Autodesk Fusion 360 part; units mm, degrees
(part 5 of 7)
extrude "Washer clearance (2)''" cut sketch "Washer clearance (1) (3)" along normal blind 0.4 bodies 36 in component "HARDWARE | M3x10 countersunk hip · reference"
ref_plane "WorkPlane11" through (0, 0, 1.2) normal (0, 0, 1) x (1, 0, 0) in component "HARDWARE | M3x10 countersunk hip · reference"
sketch "M3 underside nut (1)" plane through (0, 0, 1.2) normal (0, 0, 1) x (1, 0, 0) in component "HARDWARE | M3x10 countersunk hip · reference"
  line L0 (45.1754, 4) -> (43.5877, 6.75)
  line L1 (43.5877, 6.75) -> (40.4123, 6.75)
  line L2 (40.4123, 6.75) -> (38.8246, 4)
  line L3 (38.8246, 4) -> (40.4123, 1.25)
  line L4 (40.4123, 1.25) -> (43.5877, 1.25)
  line L5 (43.5877, 1.25) -> (45.1754, 4)
extrude "M3 underside nut (2)" add sketch "M3 underside nut (1)" along normal blind 2.4 separate body makes body 37 in component "HARDWARE | M3x10 countersunk hip · reference"
ref_plane "WorkPlane12" through (0, 0, 1.2) normal (0, 0, 1) x (1, 0, 0) in component "HARDWARE | M3x10 countersunk hip · reference"
sketch "Nut thread envelope clearance (1) (3)" plane through (0, 0, 1.2) normal (0, 0, 1) x (1, 0, 0) in component "HARDWARE | M3x10 countersunk hip · reference"
  circle A0 centre (42, 4) radius 1.65
extrude "Nut thread envelope clearance (2)''" cut sketch "Nut thread envelope clearance (1) (3)" along normal blind 2.4 bodies 37 in component "HARDWARE | M3x10 countersunk hip · reference"
ref_plane "WorkPlane1" through (0, 4, 0) normal (0, 1, 0) x (0, 0, 1) in component "HARDWARE | M2x30 knee towers · unthreaded reference"
sketch "Bolt shank (3)" plane through (0, 4, 0) normal (0, 1, 0) x (1, 0, 0) in component "HARDWARE | M2x30 knee towers · unthreaded reference"
  circle A0 centre (22.5, 10) radius 1
extrude "Bolt shank (1)''" add sketch "Bolt shank (3)" along normal blind 30 separate body makes body 38 in component "HARDWARE | M2x30 knee towers · unthreaded reference"
ref_plane "WorkPlane2" through (0, 2, 0) normal (0, 1, 0) x (0, 0, 1) in component "HARDWARE | M2x30 knee towers · unthreaded reference"
sketch "Socket head envelope (3)" plane through (0, 2, 0) normal (0, 1, 0) x (1, 0, 0) in component "HARDWARE | M2x30 knee towers · unthreaded reference"
  circle A0 centre (22.5, 10) radius 1.9
extrude "Socket head envelope (1)''" add sketch "Socket head envelope (3)" along normal blind 2 bodies 38 in component "HARDWARE | M2x30 knee towers · unthreaded reference"
ref_plane "WorkPlane3" through (0, 28, 0) normal (0, 1, 0) x (0, 0, 1) in component "HARDWARE | M2x30 knee towers · unthreaded reference"
sketch "Washer (3)" plane through (0, 28, 0) normal (0, 1, 0) x (1, 0, 0) in component "HARDWARE | M2x30 knee towers · unthreaded reference"
  circle A0 centre (22.5, 10) radius 2
extrude "Washer (1)''" add sketch "Washer (3)" along normal blind 0.4 separate body makes body 39 in component "HARDWARE | M2x30 knee towers · unthreaded reference"
ref_plane "WorkPlane4" through (0, 28, 0) normal (0, 1, 0) x (0, 0, 1) in component "HARDWARE | M2x30 knee towers · unthreaded reference"
sketch "Washer clearance (4)" plane through (0, 28, 0) normal (0, 1, 0) x (1, 0, 0) in component "HARDWARE | M2x30 knee towers · unthreaded reference"
  circle A0 centre (22.5, 10) radius 1.2
extrude "Washer clearance (1)'''" cut sketch "Washer clearance (4)" along normal blind 0.4 bodies 39 in component "HARDWARE | M2x30 knee towers · unthreaded reference"
ref_plane "WorkPlane5" through (0, 28.4, 0) normal (0, 1, 0) x (0, 0, 1) in component "HARDWARE | M2x30 knee towers · unthreaded reference"
sketch "Hex nut (3)" plane through (0, 28.4, 0) normal (0, 1, 0) x (1, 0, 0) in component "HARDWARE | M2x30 knee towers · unthreaded reference"
  line L0 (24.8094, 10) -> (23.6547, 8)
  line L1 (23.6547, 8) -> (21.3453, 8)
  line L2 (21.3453, 8) -> (20.1906, 10)
  line L3 (20.1906, 10) -> (21.3453, 12)
  line L4 (21.3453, 12) -> (23.6547, 12)
  line L5 (23.6547, 12) -> (24.8094, 10)
extrude "Hex nut (1)''" add sketch "Hex nut (3)" along normal blind 1.6 separate body makes body 40 in component "HARDWARE | M2x30 knee towers · unthreaded reference"
ref_plane "WorkPlane6" through (0, 28.4, 0) normal (0, 1, 0) x (0, 0, 1) in component "HARDWARE | M2x30 knee towers · unthreaded reference"
sketch "Nut thread envelope clearance (4)" plane through (0, 28.4, 0) normal (0, 1, 0) x (1, 0, 0) in component "HARDWARE | M2x30 knee towers · unthreaded reference"
  circle A0 centre (22.5, 10) radius 1.15
extrude "Nut thread envelope clearance (1)'''" cut sketch "Nut thread envelope clearance (4)" along normal blind 1.6 bodies 40 in component "HARDWARE | M2x30 knee towers · unthreaded reference"
ref_plane "WorkPlane7" through (0, 4, 0) normal (0, 1, 0) x (0, 0, 1) in component "HARDWARE | M2x30 knee towers · unthreaded reference"
sketch "Bolt shank (1) (3)" plane through (0, 4, 0) normal (0, 1, 0) x (1, 0, 0) in component "HARDWARE | M2x30 knee towers · unthreaded reference"
  circle A0 centre (22.5, -10) radius 1
extrude "Bolt shank (2)''" add sketch "Bolt shank (1) (3)" along normal blind 30 separate body makes body 41 in component "HARDWARE | M2x30 knee towers · unthreaded reference"
ref_plane "WorkPlane8" through (0, 2, 0) normal (0, 1, 0) x (0, 0, 1) in component "HARDWARE | M2x30 knee towers · unthreaded reference"
sketch "Socket head envelope (1) (3)" plane through (0, 2, 0) normal (0, 1, 0) x (1, 0, 0) in component "HARDWARE | M2x30 knee towers · unthreaded reference"
  circle A0 centre (22.5, -10) radius 1.9
extrude "Socket head envelope (2)''" add sketch "Socket head envelope (1) (3)" along normal blind 2 bodies 41 in component "HARDWARE | M2x30 knee towers · unthreaded reference"
ref_plane "WorkPlane9" through (0, 28, 0) normal (0, 1, 0) x (0, 0, 1) in component "HARDWARE | M2x30 knee towers · unthreaded reference"
sketch "Washer (1) (3)" plane through (0, 28, 0) normal (0, 1, 0) x (1, 0, 0) in component "HARDWARE | M2x30 knee towers · unthreaded reference"
  circle A0 centre (22.5, -10) radius 2
extrude "Washer (2)''" add sketch "Washer (1) (3)" along normal blind 0.4 separate body makes body 42 in component "HARDWARE | M2x30 knee towers · unthreaded reference"
ref_plane "WorkPlane10" through (0, 28, 0) normal (0, 1, 0) x (0, 0, 1) in component "HARDWARE | M2x30 knee towers · unthreaded reference"
sketch "Washer clearance (1) (4)" plane through (0, 28, 0) normal (0, 1, 0) x (1, 0, 0) in component "HARDWARE | M2x30 knee towers · unthreaded reference"
  circle A0 centre (22.5, -10) radius 1.2
extrude "Washer clearance (2)'''" cut sketch "Washer clearance (1) (4)" along normal blind 0.4 bodies 42 in component "HARDWARE | M2x30 knee towers · unthreaded reference"
ref_plane "WorkPlane11" through (0, 28.4, 0) normal (0, 1, 0) x (0, 0, 1) in component "HARDWARE | M2x30 knee towers · unthreaded reference"
sketch "Hex nut (1) (3)" plane through (0, 28.4, 0) normal (0, 1, 0) x (1, 0, 0) in component "HARDWARE | M2x30 knee towers · unthreaded reference"
  line L0 (24.8094, -10) -> (23.6547, -12)
  line L1 (23.6547, -12) -> (21.3453, -12)
  line L2 (21.3453, -12) -> (20.1906, -10)
  line L3 (20.1906, -10) -> (21.3453, -8)
  line L4 (21.3453, -8) -> (23.6547, -8)
  line L5 (23.6547, -8) -> (24.8094, -10)
extrude "Hex nut (2)''" add sketch "Hex nut (1) (3)" along normal blind 1.6 separate body makes body 43 in component "HARDWARE | M2x30 knee towers · unthreaded reference"
ref_plane "WorkPlane12" through (0, 28.4, 0) normal (0, 1, 0) x (0, 0, 1) in component "HARDWARE | M2x30 knee towers · unthreaded reference"
sketch "Nut thread envelope clearance (1) (4)" plane through (0, 28.4, 0) normal (0, 1, 0) x (1, 0, 0) in component "HARDWARE | M2x30 knee towers · unthreaded reference"
  circle A0 centre (22.5, -10) radius 1.15
extrude "Nut thread envelope clearance (2)'''" cut sketch "Nut thread envelope clearance (1) (4)" along normal blind 1.6 bodies 43 in component "HARDWARE | M2x30 knee towers · unthreaded reference"
sketch "Bolt shank (4)" plane through (0, 0, 0) normal (0, 0, 1) x (1, 0, 0) in component "HARDWARE | M3x50 chassis stack · unthreaded reference"
  circle A0 centre (27.7128, -16) radius 1.5
extrude "Bolt shank (1)'''" add sketch "Bolt shank (4)" along normal blind 50 separate body makes body 44 in component "HARDWARE | M3x50 chassis stack · unthreaded reference"
ref_plane "WorkPlane1" through (0, 0, -3) normal (0, 0, 1) x (1, 0, 0) in component "HARDWARE | M3x50 chassis stack · unthreaded reference"
sketch "Socket head envelope (4)" plane through (0, 0, -3) normal (0, 0, 1) x (1, 0, 0) in component "HARDWARE | M3x50 chassis stack · unthreaded reference"
  circle A0 centre (27.7128, -16) radius 2.8
extrude "Socket head envelope (1)'''" add sketch "Socket head envelope (4)" along normal blind 3 bodies 44 in component "HARDWARE | M3x50 chassis stack · unthreaded reference"
ref_plane "WorkPlane2" through (0, 0, 44) normal (0, 0, 1) x (1, 0, 0) in component "HARDWARE | M3x50 chassis stack · unthreaded reference"
sketch "Washer (4)" plane through (0, 0, 44) normal (0, 0, 1) x (1, 0, 0) in component "HARDWARE | M3x50 chassis stack · unthreaded reference"
  circle A0 centre (27.7128, -16) radius 2.75
extrude "Washer (1)'''" add sketch "Washer (4)" along normal blind 0.4 separate body makes body 45 in component "HARDWARE | M3x50 chassis stack · unthreaded reference"
ref_plane "WorkPlane3" through (0, 0, 44) normal (0, 0, 1) x (1, 0, 0) in component "HARDWARE | M3x50 chassis stack · unthreaded reference"
sketch "Washer clearance (5)" plane through (0, 0, 44) normal (0, 0, 1) x (1, 0, 0) in component "HARDWARE | M3x50 chassis stack · unthreaded reference"
  circle A0 centre (27.7128, -16) radius 1.7
extrude "Washer clearance (1)''''" cut sketch "Washer clearance (5)" along normal blind 0.4 bodies 45 in component "HARDWARE | M3x50 chassis stack · unthreaded reference"
ref_plane "WorkPlane4" through (0, 0, 44.4) normal (0, 0, 1) x (1, 0, 0) in component "HARDWARE | M3x50 chassis stack · unthreaded reference"
sketch "Hex nut (4)" plane through (0, 0, 44.4) normal (0, 0, 1) x (1, 0, 0) in component "HARDWARE | M3x50 chassis stack · unthreaded reference"
  line L0 (30.8882, -16) -> (29.3005, -13.25)
  line L1 (29.3005, -13.25) -> (26.1251, -13.25)
  line L2 (26.1251, -13.25) -> (24.5374, -16)
  line L3 (24.5374, -16) -> (26.1251, -18.75)
  line L4 (26.1251, -18.75) -> (29.3005, -18.75)
  line L5 (29.3005, -18.75) -> (30.8882, -16)
extrude "Hex nut (1)'''" add sketch "Hex nut (4)" along normal blind 2.4 separate body makes body 46 in component "HARDWARE | M3x50 chassis stack · unthreaded reference"
ref_plane "WorkPlane5" through (0, 0, 44.4) normal (0, 0, 1) x (1, 0, 0) in component "HARDWARE | M3x50 chassis stack · unthreaded reference"
sketch "Nut thread envelope clearance (5)" plane through (0, 0, 44.4) normal (0, 0, 1) x (1, 0, 0) in component "HARDWARE | M3x50 chassis stack · unthreaded reference"
  circle A0 centre (27.7128, -16) radius 1.65
extrude "Nut thread envelope clearance (1)''''" cut sketch "Nut thread envelope clearance (5)" along normal blind 2.4 bodies 46 in component "HARDWARE | M3x50 chassis stack · unthreaded reference"
sketch "Bolt shank (1) (4)" plane through (0, 0, 0) normal (0, 0, 1) x (1, 0, 0) in component "HARDWARE | M3x50 chassis stack · unthreaded reference"
  circle A0 centre (0, -32) radius 1.5
extrude "Bolt shank (2)'''" add sketch "Bolt shank (1) (4)" along normal blind 50 separate body makes body 47 in component "HARDWARE | M3x50 chassis stack · unthreaded reference"
ref_plane "WorkPlane6" through (0, 0, -3) normal (0, 0, 1) x (1, 0, 0) in component "HARDWARE | M3x50 chassis stack · unthreaded reference"
sketch "Socket head envelope (1) (4)" plane through (0, 0, -3) normal (0, 0, 1) x (1, 0, 0) in component "HARDWARE | M3x50 chassis stack · unthreaded reference"
  circle A0 centre (0, -32) radius 2.8
extrude "Socket head envelope (2)'''" add sketch "Socket head envelope (1) (4)" along normal blind 3 bodies 47 in component "HARDWARE | M3x50 chassis stack · unthreaded reference"
ref_plane "WorkPlane7" through (0, 0, 44) normal (0, 0, 1) x (1, 0, 0) in component "HARDWARE | M3x50 chassis stack · unthreaded reference"
sketch "Washer (1) (4)" plane through (0, 0, 44) normal (0, 0, 1) x (1, 0, 0) in component "HARDWARE | M3x50 chassis stack · unthreaded reference"
  circle A0 centre (0, -32) radius 2.75
extrude "Washer (2)'''" add sketch "Washer (1) (4)" along normal blind 0.4 separate body makes body 48 in component "HARDWARE | M3x50 chassis stack · unthreaded reference"
ref_plane "WorkPlane8" through (0, 0, 44) normal (0, 0, 1) x (1, 0, 0) in component "HARDWARE | M3x50 chassis stack · unthreaded reference"
sketch "Washer clearance (1) (5)" plane through (0, 0, 44) normal (0, 0, 1) x (1, 0, 0) in component "HARDWARE | M3x50 chassis stack · unthreaded reference"
  circle A0 centre (0, -32) radius 1.7
extrude "Washer clearance (2)''''" cut sketch "Washer clearance (1) (5)" along normal blind 0.4 bodies 48 in component "HARDWARE | M3x50 chassis stack · unthreaded reference"
ref_plane "WorkPlane9" through (0, 0, 44.4) normal (0, 0, 1) x (1, 0, 0) in component "HARDWARE | M3x50 chassis stack · unthreaded reference"
sketch "Hex nut (1) (4)" plane through (0, 0, 44.4) normal (0, 0, 1) x (1, 0, 0) in component "HARDWARE | M3x50 chassis stack · unthreaded reference"
  line L0 (3.1754, -32) -> (1.5877, -29.25)
  line L1 (1.5877, -29.25) -> (-1.5877, -29.25)
  line L2 (-1.5877, -29.25) -> (-3.1754, -32)
  line L3 (-3.1754, -32) -> (-1.5877, -34.75)
  line L4 (-1.5877, -34.75) -> (1.5877, -34.75)
  line L5 (1.5877, -34.75) -> (3.1754, -32)
extrude "Hex nut (2)'''" add sketch "Hex nut (1) (4)" along normal blind 2.4 separate body makes body 49 in component "HARDWARE | M3x50 chassis stack · unthreaded reference"
ref_plane "WorkPlane10" through (0, 0, 44.4) normal (0, 0, 1) x (1, 0, 0) in component "HARDWARE | M3x50 chassis stack · unthreaded reference"
sketch "Nut thread envelope clearance (1) (5)" plane through (0, 0, 44.4) normal (0, 0, 1) x (1, 0, 0) in component "HARDWARE | M3x50 chassis stack · unthreaded reference"
  circle A0 centre (0, -32) radius 1.65
extrude "Nut thread envelope clearance (2)''''" cut sketch "Nut thread envelope clearance (1) (5)" along normal blind 2.4 bodies 49 in component "HARDWARE | M3x50 chassis stack · unthreaded reference"
sketch "Bolt shank (2) (2)" plane through (0, 0, 0) normal (0, 0, 1) x (1, 0, 0) in component "HARDWARE | M3x50 chassis stack · unthreaded reference"
  circle A0 centre (-27.7128, -16) radius 1.5
extrude "Bolt shank (3)" add sketch "Bolt shank (2) (2)" along normal blind 50 separate body makes body 50 in component "HARDWARE | M3x50 chassis stack · unthreaded reference"
ref_plane "WorkPlane11" through (0, 0, -3) normal (0, 0, 1) x (1, 0, 0) in component "HARDWARE | M3x50 chassis stack · unthreaded reference"
sketch "Socket head envelope (2) (2)" plane through (0, 0, -3) normal (0, 0, 1) x (1, 0, 0) in component "HARDWARE | M3x50 chassis stack · unthreaded reference"
  circle A0 centre (-27.7128, -16) radius 2.8
extrude "Socket head envelope (3)" add sketch "Socket head envelope (2) (2)" along normal blind 3 bodies 50 in component "HARDWARE | M3x50 chassis stack · unthreaded reference"
ref_plane "WorkPlane12" through (0, 0, 44) normal (0, 0, 1) x (1, 0, 0) in component "HARDWARE | M3x50 chassis stack · unthreaded reference"
sketch "Washer (2) (2)" plane through (0, 0, 44) normal (0, 0, 1) x (1, 0, 0) in component "HARDWARE | M3x50 chassis stack · unthreaded reference"
  circle A0 centre (-27.7128, -16) radius 2.75
extrude "Washer (3)" add sketch "Washer (2) (2)" along normal blind 0.4 separate body makes body 51 in component "HARDWARE | M3x50 chassis stack · unthreaded reference"
ref_plane "WorkPlane13" through (0, 0, 44) normal (0, 0, 1) x (1, 0, 0) in component "HARDWARE | M3x50 chassis stack · unthreaded reference"
sketch "Washer clearance (2) (2)" plane through (0, 0, 44) normal (0, 0, 1) x (1, 0, 0) in component "HARDWARE | M3x50 chassis stack · unthreaded reference"
  circle A0 centre (-27.7128, -16) radius 1.7
extrude "Washer clearance (3)" cut sketch "Washer clearance (2) (2)" along normal blind 0.4 bodies 51 in component "HARDWARE | M3x50 chassis stack · unthreaded reference"
ref_plane "WorkPlane14" through (0, 0, 44.4) normal (0, 0, 1) x (1, 0, 0) in component "HARDWARE | M3x50 chassis stack · unthreaded reference"
sketch "Hex nut (2) (2)" plane through (0, 0, 44.4) normal (0, 0, 1) x (1, 0, 0) in component "HARDWARE | M3x50 chassis stack · unthreaded reference"
  line L0 (-24.5374, -16) -> (-26.1251, -13.25)
  line L1 (-26.1251, -13.25) -> (-29.3005, -13.25)
  line L2 (-29.3005, -13.25) -> (-30.8882, -16)
  line L3 (-30.8882, -16) -> (-29.3005, -18.75)
  line L4 (-29.3005, -18.75) -> (-26.1251, -18.75)
  line L5 (-26.1251, -18.75) -> (-24.5374, -16)
extrude "Hex nut (3)" add sketch "Hex nut (2) (2)" along normal blind 2.4 separate body makes body 52 in component "HARDWARE | M3x50 chassis stack · unthreaded reference"
ref_plane "WorkPlane15" through (0, 0, 44.4) normal (0, 0, 1) x (1, 0, 0) in component "HARDWARE | M3x50 chassis stack · unthreaded reference"
sketch "Nut thread envelope clearance (2) (2)" plane through (0, 0, 44.4) normal (0, 0, 1) x (1, 0, 0) in component "HARDWARE | M3x50 chassis stack · unthreaded reference"
  circle A0 centre (-27.7128, -16) radius 1.65
extrude "Nut thread envelope clearance (3)" cut sketch "Nut thread envelope clearance (2) (2)" along normal blind 2.4 bodies 52 in component "HARDWARE | M3x50 chassis stack · unthreaded reference"
sketch "Bolt shank (3) (2)" plane through (0, 0, 0) normal (0, 0, 1) x (1, 0, 0) in component "HARDWARE | M3x50 chassis stack · unthreaded reference"
  circle A0 centre (-27.7128, 16) radius 1.5
extrude "Bolt shank (4)" add sketch "Bolt shank (3) (2)" along normal blind 50 separate body makes body 53 in component "HARDWARE | M3x50 chassis stack · unthreaded reference"
ref_plane "WorkPlane16" through (0, 0, -3) normal (0, 0, 1) x (1, 0, 0) in component "HARDWARE | M3x50 chassis stack · unthreaded reference"
sketch "Socket head envelope (3) (2)" plane through (0, 0, -3) normal (0, 0, 1) x (1, 0, 0) in component "HARDWARE | M3x50 chassis stack · unthreaded reference"
  circle A0 centre (-27.7128, 16) radius 2.8
extrude "Socket head envelope (4)" add sketch "Socket head envelope (3) (2)" along normal blind 3 bodies 53 in component "HARDWARE | M3x50 chassis stack · unthreaded reference"
ref_plane "WorkPlane17" through (0, 0, 44) normal (0, 0, 1) x (1, 0, 0) in component "HARDWARE | M3x50 chassis stack · unthreaded reference"
sketch "Washer (3) (2)" plane through (0, 0, 44) normal (0, 0, 1) x (1, 0, 0) in component "HARDWARE | M3x50 chassis stack · unthreaded reference"
  circle A0 centre (-27.7128, 16) radius 2.75
extrude "Washer (4)" add sketch "Washer (3) (2)" along normal blind 0.4 separate body makes body 54 in component "HARDWARE | M3x50 chassis stack · unthreaded reference"
ref_plane "WorkPlane18" through (0, 0, 44) normal (0, 0, 1) x (1, 0, 0) in component "HARDWARE | M3x50 chassis stack · unthreaded reference"
sketch "Washer clearance (3) (2)" plane through (0, 0, 44) normal (0, 0, 1) x (1, 0, 0) in component "HARDWARE | M3x50 chassis stack · unthreaded reference"
  circle A0 centre (-27.7128, 16) radius 1.7
extrude "Washer clearance (4)" cut sketch "Washer clearance (3) (2)" along normal blind 0.4 bodies 54 in component "HARDWARE | M3x50 chassis stack · unthreaded reference"
ref_plane "WorkPlane19" through (0, 0, 44.4) normal (0, 0, 1) x (1, 0, 0) in component "HARDWARE | M3x50 chassis stack · unthreaded reference"
sketch "Hex nut (3) (2)" plane through (0, 0, 44.4) normal (0, 0, 1) x (1, 0, 0) in component "HARDWARE | M3x50 chassis stack · unthreaded reference"
  line L0 (-24.5374, 16) -> (-26.1251, 18.75)
  line L1 (-26.1251, 18.75) -> (-29.3005, 18.75)
  line L2 (-29.3005, 18.75) -> (-30.8882, 16)
  line L3 (-30.8882, 16) -> (-29.3005, 13.25)
  line L4 (-29.3005, 13.25) -> (-26.1251, 13.25)
  line L5 (-26.1251, 13.25) -> (-24.5374, 16)
extrude "Hex nut (4)" add sketch "Hex nut (3) (2)" along normal blind 2.4 separate body makes body 55 in component "HARDWARE | M3x50 chassis stack · unthreaded reference"
ref_plane "WorkPlane20" through (0, 0, 44.4) normal (0, 0, 1) x (1, 0, 0) in component "HARDWARE | M3x50 chassis stack · unthreaded reference"
sketch "Nut thread envelope clearance (3) (2)" plane through (0, 0, 44.4) normal (0, 0, 1) x (1, 0, 0) in component "HARDWARE | M3x50 chassis stack · unthreaded reference"
  circle A0 centre (-27.7128, 16) radius 1.65
extrude "Nut thread envelope clearance (4)" cut sketch "Nut thread envelope clearance (3) (2)" along normal blind 2.4 bodies 55 in component "HARDWARE | M3x50 chassis stack · unthreaded reference"
sketch "Bolt shank (4) (2)" plane through (0, 0, 0) normal (0, 0, 1) x (1, 0, 0) in component "HARDWARE | M3x50 chassis stack · unthreaded reference"
  circle A0 centre (0, 32) radius 1.5
extrude "Bolt shank (5)" add sketch "Bolt shank (4) (2)" along normal blind 50 separate body makes body 56 in component "HARDWARE | M3x50 chassis stack · unthreaded reference"
ref_plane "WorkPlane21" through (0, 0, -3) normal (0, 0, 1) x (1, 0, 0) in component "HARDWARE | M3x50 chassis stack · unthreaded reference"
sketch "Socket head envelope (4) (2)" plane through (0, 0, -3) normal (0, 0, 1) x (1, 0, 0) in component "HARDWARE | M3x50 chassis stack · unthreaded reference"
  circle A0 centre (0, 32) radius 2.8
extrude "Socket head envelope (5)" add sketch "Socket head envelope (4) (2)" along normal blind 3 bodies 56 in component "HARDWARE | M3x50 chassis stack · unthreaded reference"
ref_plane "WorkPlane22" through (0, 0, 44) normal (0, 0, 1) x (1, 0, 0) in component "HARDWARE | M3x50 chassis stack · unthreaded reference"
sketch "Washer (4) (2)" plane through (0, 0, 44) normal (0, 0, 1) x (1, 0, 0) in component "HARDWARE | M3x50 chassis stack · unthreaded reference"
  circle A0 centre (0, 32) radius 2.75
extrude "Washer (5)" add sketch "Washer (4) (2)" along normal blind 0.4 separate body makes body 57 in component "HARDWARE | M3x50 chassis stack · unthreaded reference"
ref_plane "WorkPlane23" through (0, 0, 44) normal (0, 0, 1) x (1, 0, 0) in component "HARDWARE | M3x50 chassis stack · unthreaded reference"
sketch "Washer clearance (4) (2)" plane through (0, 0, 44) normal (0, 0, 1) x (1, 0, 0) in component "HARDWARE | M3x50 chassis stack · unthreaded reference"
  circle A0 centre (0, 32) radius 1.7
extrude "Washer clearance (5)" cut sketch "Washer clearance (4) (2)" along normal blind 0.4 bodies 57 in component "HARDWARE | M3x50 chassis stack · unthreaded reference"
ref_plane "WorkPlane24" through (0, 0, 44.4) normal (0, 0, 1) x (1, 0, 0) in component "HARDWARE | M3x50 chassis stack · unthreaded reference"
sketch "Hex nut (4) (2)" plane through (0, 0, 44.4) normal (0, 0, 1) x (1, 0, 0) in component "HARDWARE | M3x50 chassis stack · unthreaded reference"
  line L0 (3.1754, 32) -> (1.5877, 34.75)
  line L1 (1.5877, 34.75) -> (-1.5877, 34.75)
  line L2 (-1.5877, 34.75) -> (-3.1754, 32)
  line L3 (-3.1754, 32) -> (-1.5877, 29.25)
  line L4 (-1.5877, 29.25) -> (1.5877, 29.25)
  line L5 (1.5877, 29.25) -> (3.1754, 32)
extrude "Hex nut (5)" add sketch "Hex nut (4) (2)" along normal blind 2.4 separate body makes body 58 in component "HARDWARE | M3x50 chassis stack · unthreaded reference"
ref_plane "WorkPlane25" through (0, 0, 44.4) normal (0, 0, 1) x (1, 0, 0) in component "HARDWARE | M3x50 chassis stack · unthreaded reference"
sketch "Nut thread envelope clearance (4) (2)" plane through (0, 0, 44.4) normal (0, 0, 1) x (1, 0, 0) in component "HARDWARE | M3x50 chassis stack · unthreaded reference"
  circle A0 centre (0, 32) radius 1.65
extrude "Nut thread envelope clearance (5)" cut sketch "Nut thread envelope clearance (4) (2)" along normal blind 2.4 bodies 58 in component "HARDWARE | M3x50 chassis stack · unthreaded reference"
sketch "Bolt shank (5)" plane through (0, 0, 0) normal (0, 0, 1) x (1, 0, 0) in component "HARDWARE | M3x50 chassis stack · unthreaded reference"
  circle A0 centre (27.7128, 16) radius 1.5
extrude "Bolt shank (6)" add sketch "Bolt shank (5)" along normal blind 50 separate body makes body 59 in component "HARDWARE | M3x50 chassis stack · unthreaded reference"
ref_plane "WorkPlane26" through (0, 0, -3) normal (0, 0, 1) x (1, 0, 0) in component "HARDWARE | M3x50 chassis stack · unthreaded reference"
sketch "Socket head envelope (5)" plane through (0, 0, -3) normal (0, 0, 1) x (1, 0, 0) in component "HARDWARE | M3x50 chassis stack · unthreaded reference"
  circle A0 centre (27.7128, 16) radius 2.8
extrude "Socket head envelope (6)" add sketch "Socket head envelope (5)" along normal blind 3 bodies 59 in component "HARDWARE | M3x50 chassis stack · unthreaded reference"
ref_plane "WorkPlane27" through (0, 0, 44) normal (0, 0, 1) x (1, 0, 0) in component "HARDWARE | M3x50 chassis stack · unthreaded reference"
sketch "Washer (5)" plane through (0, 0, 44) normal (0, 0, 1) x (1, 0, 0) in component "HARDWARE | M3x50 chassis stack · unthreaded reference"
  circle A0 centre (27.7128, 16) radius 2.75
extrude "Washer (6)" add sketch "Washer (5)" along normal blind 0.4 separate body makes body 60 in component "HARDWARE | M3x50 chassis stack · unthreaded reference"
ref_plane "WorkPlane28" through (0, 0, 44) normal (0, 0, 1) x (1, 0, 0) in component "HARDWARE | M3x50 chassis stack · unthreaded reference"
sketch "Washer clearance (5) (2)" plane through (0, 0, 44) normal (0, 0, 1) x (1, 0, 0) in component "HARDWARE | M3x50 chassis stack · unthreaded reference"
  circle A0 centre (27.7128, 16) radius 1.7
extrude "Washer clearance (6)" cut sketch "Washer clearance (5) (2)" along normal blind 0.4 bodies 60 in component "HARDWARE | M3x50 chassis stack · unthreaded reference"
ref_plane "WorkPlane29" through (0, 0, 44.4) normal (0, 0, 1) x (1, 0, 0) in component "HARDWARE | M3x50 chassis stack · unthreaded reference"
sketch "Hex nut (5)" plane through (0, 0, 44.4) normal (0, 0, 1) x (1, 0, 0) in component "HARDWARE | M3x50 chassis stack · unthreaded reference"
  line L0 (30.8882, 16) -> (29.3005, 18.75)
  line L1 (29.3005, 18.75) -> (26.1251, 18.75)
  line L2 (26.1251, 18.75) -> (24.5374, 16)
  line L3 (24.5374, 16) -> (26.1251, 13.25)
  line L4 (26.1251, 13.25) -> (29.3005, 13.25)
  line L5 (29.3005, 13.25) -> (30.8882, 16)
extrude "Hex nut (6)" add sketch "Hex nut (5)" along normal blind 2.4 separate body makes body 61 in component "HARDWARE | M3x50 chassis stack · unthreaded reference"
ref_plane "WorkPlane30" through (0, 0, 44.4) normal (0, 0, 1) x (1, 0, 0) in component "HARDWARE | M3x50 chassis stack · unthreaded reference"
sketch "Nut thread envelope clearance (5) (2)" plane through (0, 0, 44.4) normal (0, 0, 1) x (1, 0, 0) in component "HARDWARE | M3x50 chassis stack · unthreaded reference"
  circle A0 centre (27.7128, 16) radius 1.65
extrude "Nut thread envelope clearance (6)" cut sketch "Nut thread envelope clearance (5) (2)" along normal blind 2.4 bodies 61 in component "HARDWARE | M3x50 chassis stack · unthreaded reference"
ref_plane "WorkPlane1" through (0, 0, 21) normal (0, 0, 1) x (1, 0, 0) in component "PCA9685 #815 | 0x40"
sketch "Official PCA PCB envelope" plane through (0, 0, 21) normal (0, 0, 1) x (1, 0, 0) in component "PCA9685 #815 | 0x40"
  line L0 (-31.115, -28.7) -> (31.115, -28.7)
  line L1 (31.115, -28.7) -> (31.115, -3.3)
  line L2 (31.115, -3.3) -> (-31.115, -3.3)
  line L3 (-31.115, -3.3) -> (-31.115, -28.7)
extrude "Official PCA PCB envelope (1)" add sketch "Official PCA PCB envelope" along normal blind 1.57 separate body makes body 62 in component "PCA9685 #815 | 0x40"
ref_plane "WorkPlane2" through (0, 0, 21) normal (0, 0, 1) x (1, 0, 0) in component "PCA9685 #815 | 0x40"
sketch "Exact PCB mounting holes" plane through (0, 0, 21) normal (0, 0, 1) x (1, 0, 0) in component "PCA9685 #815 | 0x40"
  circle A0 centre (-27.94, -25.525) radius 1.25
  circle A1 centre (-27.94, -6.475) radius 1.25
  circle A2 centre (27.94, -25.525) radius 1.25
  circle A3 centre (27.94, -6.475) radius 1.25
extrude "Exact PCB mounting holes (1)" cut sketch "Exact PCB mounting holes" along normal blind 1.57 bodies 62 in component "PCA9685 #815 | 0x40"
ref_plane "WorkPlane3" through (0, 0, 22.57) normal (0, 0, 1) x (1, 0, 0) in component "PCA9685 #815 | 0x40"
sketch "Servo signal header envelope" plane through (0, 0, 22.57) normal (0, 0, 1) x (1, 0, 0) in component "PCA9685 #815 | 0x40"
  line L0 (-25.4, -28.573) -> (-15.24, -28.573)
  line L1 (-15.24, -28.573) -> (-15.24, -20.953)
  line L2 (-15.24, -20.953) -> (-25.4, -20.953)
  line L3 (-25.4, -20.953) -> (-25.4, -28.573)
extrude "Servo signal header envelope (1)" add sketch "Servo signal header envelope" along normal blind 8.41 bodies 62 in component "PCA9685 #815 | 0x40"
ref_plane "WorkPlane4" through (0, 0, 22.57) normal (0, 0, 1) x (1, 0, 0) in component "PCA9685 #815 | 0x40"
sketch "Servo signal header envelope (1)" plane through (0, 0, 22.57) normal (0, 0, 1) x (1, 0, 0) in component "PCA9685 #815 | 0x40"
  line L0 (-12.7, -28.573) -> (-2.54, -28.573)
  line L1 (-2.54, -28.573) -> (-2.54, -20.953)
  line L2 (-2.54, -20.953) -> (-12.7, -20.953)
  line L3 (-12.7, -20.953) -> (-12.7, -28.573)
extrude "Servo signal header envelope (2)" add sketch "Servo signal header envelope (1)" along normal blind 8.41 bodies 62 in component "PCA9685 #815 | 0x40"
ref_plane "WorkPlane5" through (0, 0, 22.57) normal (0, 0, 1) x (1, 0, 0) in component "PCA9685 #815 | 0x40"
sketch "Servo signal header envelope (2)" plane through (0, 0, 22.57) normal (0, 0, 1) x (1, 0, 0) in component "PCA9685 #815 | 0x40"
  line L0 (2.54, -28.573) -> (12.7, -28.573)
  line L1 (12.7, -28.573) -> (12.7, -20.953)
  line L2 (12.7, -20.953) -> (2.54, -20.953)
  line L3 (2.54, -20.953) -> (2.54, -28.573)
extrude "Servo signal header envelope (3)" add sketch "Servo signal header envelope (2)" along normal blind 8.41 bodies 62 in component "PCA9685 #815 | 0x40"
ref_plane "WorkPlane6" through (0, 0, 22.57) normal (0, 0, 1) x (1, 0, 0) in component "PCA9685 #815 | 0x40"
sketch "Servo signal header envelope (3)" plane through (0, 0, 22.57) normal (0, 0, 1) x (1, 0, 0) in component "PCA9685 #815 | 0x40"
  line L0 (15.24, -28.573) -> (25.4, -28.573)
  line L1 (25.4, -28.573) -> (25.4, -20.953)
  line L2 (25.4, -20.953) -> (15.24, -20.953)
  line L3 (15.24, -20.953) -> (15.24, -28.573)
extrude "Servo signal header envelope (4)" add sketch "Servo signal header envelope (3)" along normal blind 8.41 bodies 62 in component "PCA9685 #815 | 0x40"
ref_plane "WorkPlane7" through (0, 0, 22.57) normal (0, 0, 1) x (1, 0, 0) in component "PCA9685 #815 | 0x40"
sketch "Power terminal nominal envelope" plane through (0, 0, 22.57) normal (0, 0, 1) x (1, 0, 0) in component "PCA9685 #815 | 0x40"
  line L0 (-3.6, -10.51) -> (3.4, -10.51)
  line L1 (3.4, -10.51) -> (3.4, -3.51)
  line L2 (3.4, -3.51) -> (-3.6, -3.51)
  line L3 (-3.6, -3.51) -> (-3.6, -10.51)
extrude "Power terminal nominal envelope (1)" add sketch "Power terminal nominal envelope" along normal blind 8.52 bodies 62 in component "PCA9685 #815 | 0x40"
ref_plane "WorkPlane1" through (0, 0, 21) normal (0, 0, 1) x (1, 0, 0) in component "PCA9685 #815 | 0x41"
sketch "Official PCA PCB envelope (2)" plane through (0, 0, 21) normal (0, 0, 1) x (1, 0, 0) in component "PCA9685 #815 | 0x41"
  line L0 (31.115, 28.7) -> (-31.115, 28.7)
  line L1 (-31.115, 28.7) -> (-31.115, 3.3)
  line L2 (-31.115, 3.3) -> (31.115, 3.3)
  line L3 (31.115, 3.3) -> (31.115, 28.7)
extrude "Official PCA PCB envelope (1)'" add sketch "Official PCA PCB envelope (2)" along normal blind 1.57 separate body makes body 63 in component "PCA9685 #815 | 0x41"
ref_plane "WorkPlane2" through (0, 0, 21) normal (0, 0, 1) x (1, 0, 0) in component "PCA9685 #815 | 0x41"
sketch "Exact PCB mounting holes (2)" plane through (0, 0, 21) normal (0, 0, 1) x (1, 0, 0) in component "PCA9685 #815 | 0x41"
  circle A0 centre (27.94, 25.525) radius 1.25
  circle A1 centre (27.94, 6.475) radius 1.25
  circle A2 centre (-27.94, 25.525) radius 1.25
  circle A3 centre (-27.94, 6.475) radius 1.25
extrude "Exact PCB mounting holes (1)'" cut sketch "Exact PCB mounting holes (2)" along normal blind 1.57 bodies 63 in component "PCA9685 #815 | 0x41"
ref_plane "WorkPlane3" through (0, 0, 22.57) normal (0, 0, 1) x (1, 0, 0) in component "PCA9685 #815 | 0x41"
sketch "Servo signal header envelope (4)" plane through (0, 0, 22.57) normal (0, 0, 1) x (1, 0, 0) in component "PCA9685 #815 | 0x41"
  line L0 (25.4, 28.573) -> (15.24, 28.573)
  line L1 (15.24, 28.573) -> (15.24, 20.953)
  line L2 (15.24, 20.953) -> (25.4, 20.953)
  line L3 (25.4, 20.953) -> (25.4, 28.573)
extrude "Servo signal header envelope (1)'" add sketch "Servo signal header envelope (4)" along normal blind 8.41 bodies 63 in component "PCA9685 #815 | 0x41"
ref_plane "WorkPlane4" through (0, 0, 22.57) normal (0, 0, 1) x (1, 0, 0) in component "PCA9685 #815 | 0x41"
sketch "Servo signal header envelope (1) (2)" plane through (0, 0, 22.57) normal (0, 0, 1) x (1, 0, 0) in component "PCA9685 #815 | 0x41"
  line L0 (12.7, 28.573) -> (2.54, 28.573)
  line L1 (2.54, 28.573) -> (2.54, 20.953)
  line L2 (2.54, 20.953) -> (12.7, 20.953)
  line L3 (12.7, 20.953) -> (12.7, 28.573)
extrude "Servo signal header envelope (2)'" add sketch "Servo signal header envelope (1) (2)" along normal blind 8.41 bodies 63 in component "PCA9685 #815 | 0x41"
ref_plane "WorkPlane5" through (0, 0, 22.57) normal (0, 0, 1) x (1, 0, 0) in component "PCA9685 #815 | 0x41"
sketch "Servo signal header envelope (2) (2)" plane through (0, 0, 22.57) normal (0, 0, 1) x (1, 0, 0) in component "PCA9685 #815 | 0x41"
  line L0 (-2.54, 28.573) -> (-12.7, 28.573)
  line L1 (-12.7, 28.573) -> (-12.7, 20.953)
  line L2 (-12.7, 20.953) -> (-2.54, 20.953)
  line L3 (-2.54, 20.953) -> (-2.54, 28.573)
extrude "Servo signal header envelope (3)'" add sketch "Servo signal header envelope (2) (2)" along normal blind 8.41 bodies 63 in component "PCA9685 #815 | 0x41"
ref_plane "WorkPlane6" through (0, 0, 22.57) normal (0, 0, 1) x (1, 0, 0) in component "PCA9685 #815 | 0x41"
sketch "Servo signal header envelope (3) (2)" plane through (0, 0, 22.57) normal (0, 0, 1) x (1, 0, 0) in component "PCA9685 #815 | 0x41"
  line L0 (-15.24, 28.573) -> (-25.4, 28.573)
  line L1 (-25.4, 28.573) -> (-25.4, 20.953)
  line L2 (-25.4, 20.953) -> (-15.24, 20.953)
  line L3 (-15.24, 20.953) -> (-15.24, 28.573)
extrude "Servo signal header envelope (4)'" add sketch "Servo signal header envelope (3) (2)" along normal blind 8.41 bodies 63 in component "PCA9685 #815 | 0x41"
ref_plane "WorkPlane7" through (0, 0, 22.57) normal (0, 0, 1) x (1, 0, 0) in component "PCA9685 #815 | 0x41"
sketch "Power terminal nominal envelope (2)" plane through (0, 0, 22.57) normal (0, 0, 1) x (1, 0, 0) in component "PCA9685 #815 | 0x41"
  line L0 (3.6, 10.51) -> (-3.4, 10.51)
  line L1 (-3.4, 10.51) -> (-3.4, 3.51)
  line L2 (-3.4, 3.51) -> (3.6, 3.51)
  line L3 (3.6, 3.51) -> (3.6, 10.51)
extrude "Power terminal nominal envelope (1)'" add sketch "Power terminal nominal envelope (2)" along normal blind 8.52 bodies 63 in component "PCA9685 #815 | 0x41"
ref_plane "WorkPlane1" through (0, 0, 44.4) normal (0, 0, 1) x (1, 0, 0) in component "BRAIN | Adafruit Feather ESP32 V2 #5400"
sketch "Official Feather PCB envelope" plane through (0, 0, 44.4) normal (0, 0, 1) x (1, 0, 0) in component "BRAIN | Adafruit Feather ESP32 V2 #5400"
  line L0 (-25.4, -11.43) -> (25.4, -11.43)
  line L1 (25.4, -11.43) -> (25.4, 11.43)
  line L2 (25.4, 11.43) -> (-25.4, 11.43)
  line L3 (-25.4, 11.43) -> (-25.4, -11.43)
extrude "Official Feather PCB envelope (1)" add sketch "Official Feather PCB envelope" along normal blind 1.57 separate body makes body 64 in component "BRAIN | Adafruit Feather ESP32 V2 #5400"
ref_plane "WorkPlane2" through (0, 0, 44.4) normal (0, 0, 1) x (1, 0, 0) in component "BRAIN | Adafruit Feather ESP32 V2 #5400"
sketch "Feather exact M2 mounting holes" plane through (0, 0, 44.4) normal (0, 0, 1) x (1, 0, 0) in component "BRAIN | Adafruit Feather ESP32 V2 #5400"
  circle A0 centre (-22.86, -8.89) radius 1.25
  circle A1 centre (-22.86, 8.89) radius 1.25
  circle A2 centre (22.86, -8.89) radius 1.25
  circle A3 centre (22.86, 8.89) radius 1.25
extrude "Feather exact M2 mounting holes (1)" cut sketch "Feather exact M2 mounting holes" along normal blind 1.57 bodies 64 in component "BRAIN | Adafruit Feather ESP32 V2 #5400"
ref_plane "WorkPlane3" through (0, 0, 45.97) normal (0, 0, 1) x (1, 0, 0) in component "BRAIN | Adafruit Feather ESP32 V2 #5400"
sketch "USB C service port" plane through (0, 0, 45.97) normal (0, 0, 1) x (1, 0, 0) in component "BRAIN | Adafruit Feather ESP32 V2 #5400"
  line L0 (-26.543, -4.47) -> (-19.193, -4.47)
  line L1 (-19.193, -4.47) -> (-19.193, 4.47)
  line L2 (-19.193, 4.47) -> (-26.543, 4.47)
  line L3 (-26.543, 4.47) -> (-26.543, -4.47)
extrude "USB C service port (1)" add sketch "USB C service port" along normal blind 3.23 bodies 64 in component "BRAIN | Adafruit Feather ESP32 V2 #5400"
ref_plane "WorkPlane4" through (0, 0, 45.97) normal (0, 0, 1) x (1, 0, 0) in component "BRAIN | Adafruit Feather ESP32 V2 #5400"
sketch "Single cell BAT connector NOT for 2S" plane through (0, 0, 45.97) normal (0, 0, 1) x (1, 0, 0) in component "BRAIN | Adafruit Feather ESP32 V2 #5400"
  line L0 (-18.4145, 3.374) -> (-10.4145, 3.374)
  line L1 (-10.4145, 3.374) -> (-10.4145, 10.874)
  line L2 (-10.4145, 10.874) -> (-18.4145, 10.874)
  line L3 (-18.4145, 10.874) -> (-18.4145, 3.374)
extrude "Single cell BAT connector NOT for 2S (1)" add sketch "Single cell BAT connector NOT for 2S" along normal blind 4.8 bodies 64 in component "BRAIN | Adafruit Feather ESP32 V2 #5400"
ref_plane "WorkPlane5" through (0, 0, 45.97) normal (0, 0, 1) x (1, 0, 0) in component "BRAIN | Adafruit Feather ESP32 V2 #5400"
sketch "ESP32 shield approximate envelope" plane through (0, 0, 45.97) normal (0, 0, 1) x (1, 0, 0) in component "BRAIN | Adafruit Feather ESP32 V2 #5400"
  line L0 (-5, -8) -> (19, -8)
  line L1 (19, -8) -> (19, 8)
  line L2 (19, 8) -> (-5, 8)
  line L3 (-5, 8) -> (-5, -8)
extrude "ESP32 shield approximate envelope (1)" add sketch "ESP32 shield approximate envelope" along normal blind 2.5 bodies 64 in component "BRAIN | Adafruit Feather ESP32 V2 #5400"
ref_plane "WorkPlane1" through (0, 0, -1) normal (0, 0, 1) x (1, 0, 0) in component "POWER | Pololu D42V110F5 #5671"
sketch "Pololu PCB31.75x43.18" plane through (0, 0, -1) normal (0, 0, 1) x (1, 0, 0) in component "POWER | Pololu D42V110F5 #5671"
  line L0 (-15.875, -21.59) -> (15.875, -21.59)
  line L1 (15.875, -21.59) -> (15.875, 21.59)
  line L2 (15.875, 21.59) -> (-15.875, 21.59)
  line L3 (-15.875, 21.59) -> (-15.875, -21.59)
extrude "Pololu PCB31.75x43.18 (1)" add sketch "Pololu PCB31.75x43.18" along normal blind 1.6 separate body makes body 65 in component "POWER | Pololu D42V110F5 #5671"
ref_plane "WorkPlane2" through (0, 0, -1) normal (0, 0, 1) x (1, 0, 0) in component "POWER | Pololu D42V110F5 #5671"
sketch "Verified regulator M2 hole pattern" plane through (0, 0, -1) normal (0, 0, 1) x (1, 0, 0) in component "POWER | Pololu D42V110F5 #5671"
  circle A0 centre (-13.716, -19.431) radius 1.09
  circle A1 centre (11.684, -19.431) radius 1.09
  circle A2 centre (-13.716, 19.431) radius 1.09
  circle A3 centre (11.684, 19.431) radius 1.09
extrude "Verified regulator M2 hole pattern (1)" cut sketch "Verified regulator M2 hole pattern" along normal blind 1.6 bodies 65 in component "POWER | Pololu D42V110F5 #5671"
ref_plane "WorkPlane3" through (0, 0, 0.6) normal (0, 0, 1) x (1, 0, 0) in component "POWER | Pololu D42V110F5 #5671"
sketch "9mm regulator overall height envelope" plane through (0, 0, 0.6) normal (0, 0, 1) x (1, 0, 0) in component "POWER | Pololu D42V110F5 #5671"
  line L0 (-10, -13) -> (10, -13)
  line L1 (10, -13) -> (10, 13)
  line L2 (10, 13) -> (-10, 13)
  line L3 (-10, 13) -> (-10, -13)
extrude "9mm regulator overall height envelope (1)" add sketch "9mm regulator overall height envelope" along normal blind 7.4 bodies 65 in component "POWER | Pololu D42V110F5 #5671"
ref_plane "WorkPlane1" through (0, 0, 40.4) normal (0, 0, 1) x (1, 0, 0) in component "POWER | Pololu D24V10F5 #2831"
sketch "12.7x17.78 logic PCB" plane through (0, 0, 40.4) normal (0, 0, 1) x (1, 0, 0) in component "POWER | Pololu D24V10F5 #2831"
  line L0 (-8.89, 15.15) -> (8.89, 15.15)
  line L1 (8.89, 15.15) -> (8.89, 27.85)
  line L2 (8.89, 27.85) -> (-8.89, 27.85)
  line L3 (-8.89, 27.85) -> (-8.89, 15.15)
extrude "12.7x17.78 logic PCB (1)" add sketch "12.7x17.78 logic PCB" along normal blind 1.6 separate body makes body 66 in component "POWER | Pololu D24V10F5 #2831"
ref_plane "WorkPlane2" through (0, 0, 42) normal (0, 0, 1) x (1, 0, 0) in component "POWER | Pololu D24V10F5 #2831"
sketch "Logic regulator overall3.56height" plane through (0, 0, 42) normal (0, 0, 1) x (1, 0, 0) in component "POWER | Pololu D24V10F5 #2831"
  line L0 (-7, 17) -> (7, 17)
  line L1 (7, 17) -> (7, 26)
  line L2 (7, 26) -> (-7, 26)
  line L3 (-7, 26) -> (-7, 17)
extrude "Logic regulator overall3.56height (1)" add sketch "Logic regulator overall3.56height" along normal blind 1.96 bodies 66 in component "POWER | Pololu D24V10F5 #2831"
ref_plane "WorkPlane1" through (0, 0, -26) normal (0, 0, 1) x (1, 0, 0) in component "BATTERY | Gens ace 450mAh 2S XT30 · pouch envelope"
sketch "Official43x23x13 battery envelope" plane through (0, 0, -26) normal (0, 0, 1) x (1, 0, 0) in component "BATTERY | Gens ace 450mAh 2S XT30 · pouch envelope"
  line L0 (-21.5, -11.5) -> (21.5, -11.5)
  line L1 (21.5, -11.5) -> (21.5, 11.5)
  line L2 (21.5, 11.5) -> (-21.5, 11.5)
  line L3 (-21.5, 11.5) -> (-21.5, -11.5)
extrude "Official43x23x13 battery envelope (1)" add sketch "Official43x23x13 battery envelope" along normal blind 13 separate body makes body 67 in component "BATTERY | Gens ace 450mAh 2S XT30 · pouch envelope"
ref_plane "WorkPlane1" through (0, 0, 12) normal (0, 0, 1) x (1, 0, 0) in component "HARDWARE | PCA M2x14 · unthreaded reference"
sketch "Bolt shank (6)" plane through (0, 0, 12) normal (0, 0, 1) x (1, 0, 0) in component "HARDWARE | PCA M2x14 · unthreaded reference"
  circle A0 centre (-27.94, -25.525) radius 1
extrude "Bolt shank (1)''''" add sketch "Bolt shank (6)" along normal blind 14 separate body makes body 68 in component "HARDWARE | PCA M2x14 · unthreaded reference"
ref_plane "WorkPlane2" through (0, 0, 10) normal (0, 0, 1) x (1, 0, 0) in component "HARDWARE | PCA M2x14 · unthreaded reference"
sketch "Socket head envelope (6)" plane through (0, 0, 10) normal (0, 0, 1) x (1, 0, 0) in component "HARDWARE | PCA M2x14 · unthreaded reference"
  circle A0 centre (-27.94, -25.525) radius 1.9
extrude "Socket head envelope (1)''''" add sketch "Socket head envelope (6)" along normal blind 2 bodies 68 in component "HARDWARE | PCA M2x14 · unthreaded reference"
ref_plane "WorkPlane3" through (0, 0, 22.57) normal (0, 0, 1) x (1, 0, 0) in component "HARDWARE | PCA M2x14 · unthreaded reference"
sketch "Washer (6)" plane through (0, 0, 22.57) normal (0, 0, 1) x (1, 0, 0) in component "HARDWARE | PCA M2x14 · unthreaded reference"
  circle A0 centre (-27.94, -25.525) radius 2
extrude "Washer (1)''''" add sketch "Washer (6)" along normal blind 0.4 separate body makes body 69 in component "HARDWARE | PCA M2x14 · unthreaded reference"
ref_plane "WorkPlane4" through (0, 0, 22.57) normal (0, 0, 1) x (1, 0, 0) in component "HARDWARE | PCA M2x14 · unthreaded reference"
sketch "Washer clearance (6)" plane through (0, 0, 22.57) normal (0, 0, 1) x (1, 0, 0) in component "HARDWARE | PCA M2x14 · unthreaded reference"
  circle A0 centre (-27.94, -25.525) radius 1.2
extrude "Washer clearance (1)'''''" cut sketch "Washer clearance (6)" along normal blind 0.4 bodies 69 in component "HARDWARE | PCA M2x14 · unthreaded reference"
ref_plane "WorkPlane5" through (0, 0, 22.97) normal (0, 0, 1) x (1, 0, 0) in component "HARDWARE | PCA M2x14 · unthreaded reference"
sketch "Hex nut (6)" plane through (0, 0, 22.97) normal (0, 0, 1) x (1, 0, 0) in component "HARDWARE | PCA M2x14 · unthreaded reference"
  line L0 (-25.6306, -25.525) -> (-26.7853, -23.525)
  line L1 (-26.7853, -23.525) -> (-29.0947, -23.525)
  line L2 (-29.0947, -23.525) -> (-30.2494, -25.525)
  line L3 (-30.2494, -25.525) -> (-29.0947, -27.525)
  line L4 (-29.0947, -27.525) -> (-26.7853, -27.525)
  line L5 (-26.7853, -27.525) -> (-25.6306, -25.525)
extrude "Hex nut (1)''''" add sketch "Hex nut (6)" along normal blind 1.6 separate body makes body 70 in component "HARDWARE | PCA M2x14 · unthreaded reference"
ref_plane "WorkPlane6" through (0, 0, 22.97) normal (0, 0, 1) x (1, 0, 0) in component "HARDWARE | PCA M2x14 · unthreaded reference"
sketch "Nut thread envelope clearance (6)" plane through (0, 0, 22.97) normal (0, 0, 1) x (1, 0, 0) in component "HARDWARE | PCA M2x14 · unthreaded reference"
  circle A0 centre (-27.94, -25.525) radius 1.15
extrude "Nut thread envelope clearance (1)'''''" cut sketch "Nut thread envelope clearance (6)" along normal blind 1.6 bodies 70 in component "HARDWARE | PCA M2x14 · unthreaded reference"
ref_plane "WorkPlane7" through (0, 0, 12) normal (0, 0, 1) x (1, 0, 0) in component "HARDWARE | PCA M2x14 · unthreaded reference"
sketch "Bolt shank (1) (5)" plane through (0, 0, 12) normal (0, 0, 1) x (1, 0, 0) in component "HARDWARE | PCA M2x14 · unthreaded reference"
  circle A0 centre (-27.94, -6.475) radius 1
extrude "Bolt shank (2)''''" add sketch "Bolt shank (1) (5)" along normal blind 14 separate body makes body 71 in component "HARDWARE | PCA M2x14 · unthreaded reference"
ref_plane "WorkPlane8" through (0, 0, 10) normal (0, 0, 1) x (1, 0, 0) in component "HARDWARE | PCA M2x14 · unthreaded reference"
sketch "Socket head envelope (1) (5)" plane through (0, 0, 10) normal (0, 0, 1) x (1, 0, 0) in component "HARDWARE | PCA M2x14 · unthreaded reference"
  circle A0 centre (-27.94, -6.475) radius 1.9
extrude "Socket head envelope (2)''''" add sketch "Socket head envelope (1) (5)" along normal blind 2 bodies 71 in component "HARDWARE | PCA M2x14 · unthreaded reference"
ref_plane "WorkPlane9" through (0, 0, 22.57) normal (0, 0, 1) x (1, 0, 0) in component "HARDWARE | PCA M2x14 · unthreaded reference"
sketch "Washer (1) (5)" plane through (0, 0, 22.57) normal (0, 0, 1) x (1, 0, 0) in component "HARDWARE | PCA M2x14 · unthreaded reference"
  circle A0 centre (-27.94, -6.475) radius 2
extrude "Washer (2)''''" add sketch "Washer (1) (5)" along normal blind 0.4 separate body makes body 72 in component "HARDWARE | PCA M2x14 · unthreaded reference"
ref_plane "WorkPlane10" through (0, 0, 22.57) normal (0, 0, 1) x (1, 0, 0) in component "HARDWARE | PCA M2x14 · unthreaded reference"
sketch "Washer clearance (1) (6)" plane through (0, 0, 22.57) normal (0, 0, 1) x (1, 0, 0) in component "HARDWARE | PCA M2x14 · unthreaded reference"
  circle A0 centre (-27.94, -6.475) radius 1.2
extrude "Washer clearance (2)'''''" cut sketch "Washer clearance (1) (6)" along normal blind 0.4 bodies 72 in component "HARDWARE | PCA M2x14 · unthreaded reference"
ref_plane "WorkPlane11" through (0, 0, 22.97) normal (0, 0, 1) x (1, 0, 0) in component "HARDWARE | PCA M2x14 · unthreaded reference"
sketch "Hex nut (1) (5)" plane through (0, 0, 22.97) normal (0, 0, 1) x (1, 0, 0) in component "HARDWARE | PCA M2x14 · unthreaded reference"
  line L0 (-25.6306, -6.475) -> (-26.7853, -4.475)
  line L1 (-26.7853, -4.475) -> (-29.0947, -4.475)
  line L2 (-29.0947, -4.475) -> (-30.2494, -6.475)
  line L3 (-30.2494, -6.475) -> (-29.0947, -8.475)
  line L4 (-29.0947, -8.475) -> (-26.7853, -8.475)
  line L5 (-26.7853, -8.475) -> (-25.6306, -6.475)
extrude "Hex nut (2)''''" add sketch "Hex nut (1) (5)" along normal blind 1.6 separate body makes body 73 in component "HARDWARE | PCA M2x14 · unthreaded reference"
ref_plane "WorkPlane12" through (0, 0, 22.97) normal (0, 0, 1) x (1, 0, 0) in component "HARDWARE | PCA M2x14 · unthreaded reference"
sketch "Nut thread envelope clearance (1) (6)" plane through (0, 0, 22.97) normal (0, 0, 1) x (1, 0, 0) in component "HARDWARE | PCA M2x14 · unthreaded reference"
  circle A0 centre (-27.94, -6.475) radius 1.15
extrude "Nut thread envelope clearance (2)'''''" cut sketch "Nut thread envelope clearance (1) (6)" along normal blind 1.6 bodies 73 in component "HARDWARE | PCA M2x14 · unthreaded reference"
ref_plane "WorkPlane13" through (0, 0, 12) normal (0, 0, 1) x (1, 0, 0) in component "HARDWARE | PCA M2x14 · unthreaded reference"
sketch "Bolt shank (2) (3)" plane through (0, 0, 12) normal (0, 0, 1) x (1, 0, 0) in component "HARDWARE | PCA M2x14 · unthreaded reference"
  circle A0 centre (27.94, -25.525) radius 1
extrude "Bolt shank (3)'" add sketch "Bolt shank (2) (3)" along normal blind 14 separate body makes body 74 in component "HARDWARE | PCA M2x14 · unthreaded reference"
ref_plane "WorkPlane14" through (0, 0, 10) normal (0, 0, 1) x (1, 0, 0) in component "HARDWARE | PCA M2x14 · unthreaded reference"
sketch "Socket head envelope (2) (3)" plane through (0, 0, 10) normal (0, 0, 1) x (1, 0, 0) in component "HARDWARE | PCA M2x14 · unthreaded reference"
  circle A0 centre (27.94, -25.525) radius 1.9
extrude "Socket head envelope (3)'" add sketch "Socket head envelope (2) (3)" along normal blind 2 bodies 74 in component "HARDWARE | PCA M2x14 · unthreaded reference"
ref_plane "WorkPlane15" through (0, 0, 22.57) normal (0, 0, 1) x (1, 0, 0) in component "HARDWARE | PCA M2x14 · unthreaded reference"
sketch "Washer (2) (3)" plane through (0, 0, 22.57) normal (0, 0, 1) x (1, 0, 0) in component "HARDWARE | PCA M2x14 · unthreaded reference"
  circle A0 centre (27.94, -25.525) radius 2